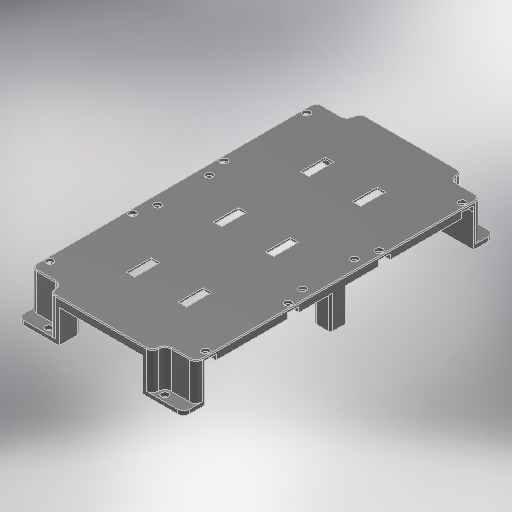
# Autodesk Inventor part: 3D_circuit-mount
Saved by Autodesk Inventor 2025.3 (Build 293356030, 356C)
## iProperties
Created: 2026-09-07
Part Number: 3D_circuit-mount
Material: 一般
Document SubType Name: Modeling
Designer: ibuki_ono
Density: 1 g/cm^3
Appearance: 滑らか - 黒
Author: ibuki_ono
## iProperties of the stored document 3D_circuit-mount_3D プリント.ipt
Created: 2026-09-07
Part Number: 3D_circuit-mount_3D プリント
Material: 一般
Document SubType Name: Modeling
Designer: ibuki_ono
Density: 1 g/cm^3
Appearance: 既定
Author: ibuki_ono
Autodesk Inventor part; units mm, degrees
ref_plane "YZ Plane" through (0, 0, 0) normal (1, 0, 0) x (0, 1, 0)
ref_plane "XZ Plane" through (0, 0, 0) normal (0, 1, 0) x (-1, 0, 0)
ref_plane "XY Plane" through (0, 0, 0) normal (0, 0, 1) x (1, 0, 0)
sketch "スケッチ1" plane through (0, 0, 0) normal (0, 1, 0) x (-1, 0, 0)
  line L0 (-28, 72) -> (28, 72) construction
  line L1 (28, 72) -> (28, -72) construction
  line L2 (28, -72) -> (-28, -72) construction
  line L3 (-28, -72) -> (-28, 72) construction
  line L4 (-28, 72) -> (28, -72) construction
  line L5 (28, 72) -> (-28, -72) construction
  line L6 (-40, -75) -> (40, -75)
  line L7 (40, -75) -> (40, 75)
  line L8 (40, 75) -> (-40, 75)
  line L9 (-40, 75) -> (-40, -75)
  line L10 (-40, -75) -> (40, 75) construction
  line L11 (40, -75) -> (-40, 75) construction
  point P0 (0, 0)
  dimension "d0" = 56
  dimension "d1" = 144
  dimension "d5" = 80
  dimension "d6" = 150
  constraints: 24 end point, 4 midpoint, 4 parallel, 2 horizontal, 2 perpendicular
  measures "d0" distance of L1.end L2.end
  measures "d1" distance of L0.end L1.end
  measures "d5" distance of L8.end L7.end
  measures "d6" distance of L7.end L6.end
extrude "押し出し1" add sketch "スケッチ1" along normal mid plane 2
sketch "スケッチ2" plane through (0, 1, 0) normal (0, 1, 0) x (1, 0, 0)
  line L0 (28, -72) -> (-28, -72) construction
  line L1 (-28, -72) -> (-28, 72) construction
  line L2 (-28, 72) -> (28, 72) construction
  line L3 (28, 72) -> (28, -72) construction
  line L4 (28, -72) -> (-28, 72) construction
  line L5 (-28, -72) -> (28, 72) construction
  line L6 (-40, 75) -> (-40, -75) projected
  line L7 (-40, -75) -> (40, -75) projected
  line L8 (40, -75) -> (40, 75) projected
  line L9 (40, 75) -> (-40, 75) projected
  circle A0 centre (-28, -72) radius 3
  circle A1 centre (28, -72) radius 3
  circle A2 centre (-28, 72) radius 3
  circle A3 centre (28, 72) radius 3
  line L10 (-40, -75) -> (40, -75) projected
  line L11 (40, 75) -> (-40, 75) projected
  line L12 (-28, -69) -> (-40, -69)
  line L13 (28, -69) -> (40, -69)
  line L14 (28, 69) -> (40, 69)
  line L15 (-28, 69) -> (-40, 69)
  line L16 (-25, -72) -> (-25, -75)
  line L17 (25, -72) -> (25, -75)
  line L18 (25, 72) -> (25, 75)
  line L19 (-25, 72) -> (-25, 75)
  point P0 (0, 0)
  dimension "d7" = 56
  dimension "d8" = 144
  constraints: 28 end point, 20 point on line, 8 point on circle, 7 tangent, 5 perpendicular, 4 centre point, 4 coincident, 2 midpoint, 2 parallel, 1 horizontal
  measures "d7" distance of L1.end L2.end
  measures "d8" distance of L0.end L1.end
extrude "押し出し2" add sketch "スケッチ2" along normal blind 18 contours L15 A2 L19 L9 L18 A3 L14 L8 L13 A1 L17 L7 L16 A0 L12 L6
sketch "スケッチ3" plane through (0, -1, 0) normal (0, -1, 0) x (1, 0, 0)
  arc A0 (-25, -72) -> (-28, -69) centre (-28, -72) ccw projected
  line L0 (-28, -69) -> (-40, -69) projected
  line L1 (-40, -69) -> (-40, 69) projected
  line L2 (-40, 69) -> (-28, 69) projected
  arc A1 (-28, 69) -> (-25, 72) centre (-28, 72) ccw projected
  line L3 (-25, 72) -> (-25, 75) projected
  line L4 (-25, 75) -> (25, 75) projected
  line L5 (25, 75) -> (25, 72) projected
  arc A2 (25, 72) -> (28, 69) centre (28, 72) ccw projected
  line L6 (28, 69) -> (40, 69) projected
  line L7 (40, 69) -> (40, -69) projected
  line L8 (40, -69) -> (28, -69) projected
  arc A3 (28, -69) -> (25, -72) centre (28, -72) ccw projected
  line L9 (25, -72) -> (25, -75) projected
  line L10 (25, -75) -> (-25, -75) projected
  line L11 (-25, -75) -> (-25, -72) projected
  line L12 (40, 65) -> (-40, 65)
  line L13 (40, -65) -> (-40, -65)
  line L14 (-40, 75) -> (-40, -75) projected
  line L15 (40, 75) -> (-40, 75) projected
  line L16 (-20, 75) -> (20, 75)
  line L17 (20, 75) -> (20, 65)
  line L18 (20, 65) -> (-20, 65)
  line L19 (-20, 65) -> (-20, 75)
  line L20 (-20, -65) -> (20, -65)
  line L21 (20, -65) -> (20, -75)
  line L22 (20, -75) -> (-20, -75)
  line L23 (-20, -75) -> (-20, -65)
  point P0 (0, 0)
  point P1 (0, 75)
  point P2 (0, -75)
  point P3 (-40, -65)
  dimension "d11" = 4
  dimension "d12" = 4
  dimension "d13" = 5
  dimension "d14" = 5
  constraints: 20 end point, 8 point on line, 4 midpoint, 4 parallel, 4 perpendicular, 2 horizontal
  measures "d11" distance between parallel lines of L6 L12
  measures "d12" distance between parallel lines of L8 L13
  measures "d13" distance between parallel lines of L17 L5
  measures "d14" distance between parallel lines of L9 L21
extrude "押し出し3" cut sketch "スケッチ3" against normal blind 16 contours L23 L13 L21 L10 | L1 L12 L7 L13 | L19 L4 L17 L12
sketch "スケッチ4" plane through (0, 15, 0) normal (0, -1, 0) x (1, 0, 0)
  line L0 (40, 65) -> (40, -65) projected
  line L1 (-40, -65) -> (-40, 65) projected
  line L2 (40, 4) -> (32, 4)
  line L3 (32, 4) -> (32, -4)
  line L4 (32, -4) -> (40, -4)
  line L5 (40, -4) -> (40, 4)
  line L6 (-40, 4) -> (-32, 4)
  line L7 (-32, 4) -> (-32, -4)
  line L8 (-32, -4) -> (-40, -4)
  line L9 (-40, -4) -> (-40, 4)
  point P0 (0, 0)
  point P1 (40, 0)
  point P2 (-40, 0)
  dimension "d17" = 8
  dimension "d18" = 8
  dimension "d19" = 8
  dimension "d20" = 8
  constraints: 16 end point, 4 midpoint, 4 parallel, 2 horizontal, 2 perpendicular, 2 point on line
  measures "d17" distance of L4.end L3.end
  measures "d18" distance of L3.end L2.end
  measures "d19" distance of L7.end L8.end
  measures "d20" distance of L6.end L7.end
extrude "押し出し4" add sketch "スケッチ4" along normal up to surface (16 mm away)
sketch "スケッチ5" plane through (0, 15, 0) normal (0, -1, 0) x (1, 0, 0)
  line L0 (-37.5, 62) -> (37.5, 62) construction
  line L1 (37.5, 62) -> (37.5, 22) construction
  line L2 (37.5, 22) -> (-37.5, 22) construction
  line L3 (-37.5, 22) -> (-37.5, 62) construction
  line L4 (-37.5, 62) -> (37.5, 22) construction
  line L5 (37.5, 62) -> (-37.5, 22) construction
  point P0 (0, 0)
  point P1 (0, 42)
  dimension "d23" = 75
  dimension "d24" = 40
  dimension "d25" = 42
  constraints: 12 end point, 4 coincident, 2 midpoint, 2 parallel, 1 horizontal, 1 perpendicular, 1 vertical alignment
  measures "d23" distance of L1.end L2.end
  measures "d24" distance of L0.end L1.end
  measures "d25" distance of point (0, 0) point (0, 42)
hole "穴1" at (37.5, 15, 62) at (37.5, 15, 22) at (-37.5, 15, 22) at (-37.5, 15, 62) direction (0, 1, 0) diameter 3.5 end through all
sketch "スケッチ6" plane through (0, 15, 0) normal (0, -1, 0) x (1, 0, 0)
  circle A0 centre (37.5, 62) radius 1.75 projected
  line L0 (35.9123, 59.25) -> (34.3246, 62)
  line L1 (34.3246, 62) -> (35.9123, 64.75)
  line L2 (35.9123, 64.75) -> (39.0877, 64.75)
  line L3 (39.0877, 64.75) -> (40.6754, 62)
  line L4 (40.6754, 62) -> (39.0877, 59.25)
  line L5 (39.0877, 59.25) -> (35.9123, 59.25)
  line L6 (40, 65) -> (40, 4) projected
  line L7 (39.0877, 64.75) -> (40, 64.75)
  line L8 (39.0877, 59.25) -> (40, 59.25)
  point P0 (0, 0)
  point P1 (40, 60.8301)
  point P2 (40, 63.1699)
  dimension "d33" = 5.5
  constraints: 16 end point, 2 perpendicular, 2 point on line, 1 coincident, 1 horizontal alignment, 13 other
  measures "d33" distance between parallel lines of L1 L4
extrude "押し出し5" cut sketch "スケッチ6" against normal blind 2.6
pattern_linear "矩形状パターン1" count 2 spacing 40 along (0, 0, -1) of "押し出し5"
mirror "ミラー1" about plane through (0, 0, 0) normal (1, 0, 0) of "押し出し5", "矩形状パターン1"
mirror "ミラー2" about plane through (0, 0, 0) normal (0, 0, 1) of "穴1", "押し出し5", "矩形状パターン1", "ミラー1"
sketch "スケッチ7" plane through (0, 15, 0) normal (0, -1, 0) x (1, 0, 0)
  line L0 (-25, -60) -> (25, -60)
  line L1 (25, -60) -> (25, 60)
  line L2 (25, 60) -> (-25, 60)
  line L3 (-25, 60) -> (-25, -60)
  line L4 (-25, -60) -> (25, 60) construction
  line L5 (25, -60) -> (-25, 60) construction
  point P0 (0, 0)
  dimension "d39" = 50
  dimension "d40" = 120
  constraints: 12 end point, 2 midpoint, 2 parallel, 1 horizontal, 1 perpendicular
  measures "d39" distance of L2.end L1.end
  measures "d40" distance of L1.end L0.end
extrude "押し出し6" cut sketch "スケッチ7" against normal blind 3
sketch "スケッチ8" plane through (0, 1, 0) normal (0, 1, 0) x (1, 0, 0)
  arc A0 (-25, -72) -> (-28, -69) centre (-28, -72) ccw projected
  arc A1 (28, -69) -> (25, -72) centre (28, -72) ccw projected
  arc A2 (25, 72) -> (28, 69) centre (28, 72) ccw projected
  arc A3 (-28, 69) -> (-25, 72) centre (-28, 72) ccw projected
  point P0 (0, 0)
  constraints: 4 coincident
hole "穴2" at (-28, 1, 72) at (28, 1, 72) at (28, 1, -72) at (-28, 1, -72) direction (0, -1, 0) diameter 3.5 end through all
fillet "フィレット1" radius 3 12 edges at (40, 0, 75) (40, 0, -75) (-40, 0, 75) (-40, 0, -75) (-25, 10, -75) (-40, 10, -69) (25, 10, -75) (40, 10, -69) (40, 10, 69) (25, 10, 75) (-25, 10, 75) (-40, 10, 69)
fillet "フィレット2" radius 1 12 edges at (40, 7, 4) (40, 7, -4) (32, 7, 4) (32, 7, -4) (-40, 7, 4) (-40, 7, -4) (-32, 7, 4) (-32, 7, -4) (20, 7, -65) (-20, 7, -65) (20, 7, 65) (-20, 7, 65)
fillet "フィレット3" radius 2 4 edges at (25, 16.5, 60) (-25, 16.5, 60) (-25, 16.5, -60) (25, 16.5, -60)
sketch "スケッチ9" plane through (0, 19, 0) normal (0, 1, 0) x (1, 0, 0)
  line L0 (-10.5, -6) -> (-14.5, -6)
  line L1 (-14.5, -6) -> (-14.5, 6)
  line L2 (-14.5, 6) -> (-10.5, 6)
  line L3 (-10.5, 6) -> (-10.5, -6)
  line L4 (-10.5, -6) -> (-14.5, 6) construction
  line L5 (-14.5, -6) -> (-10.5, 6) construction
  point P0 (0, 0)
  point P1 (-12.5, 0)
  dimension "d53" = 4
  dimension "d54" = 12
  dimension "d55" = 12.5
  constraints: 12 end point, 2 midpoint, 2 parallel, 1 horizontal, 1 horizontal alignment, 1 perpendicular
  measures "d53" distance of L1.end L2.end
  measures "d54" distance of L0.end L1.end
  measures "d55" distance of point (0, 0) point (-12.5, 0)
extrude "押し出し7" cut sketch "スケッチ9" against normal through all
mirror "ミラー3" about plane through (0, 0, 0) normal (1, 0, 0) of "押し出し7"
pattern_linear "矩形状パターン2" count 3 spacing 42 along (0, 0, -1) of "押し出し7", "ミラー3" first direction both ways yes
chamfer "面取り1" distance 0.4 angle 45 24 edges at (24.1213, 19, 74.1213) (25, 19, 72.0001) (0, 19, 75) (-24.1213, 19, 74.1213) (-25, 19, 72.0001) (-25.8787, 19, 69.8787) (-32.5, 19, 69) (-39.1213, 19, 68.1213) (-40, 19, 0) (-39.1213, 19, -68.1213) (-32.5001, 19, -69) (-25, 19, -72.0001) (-25.8787, 19, -69.8787) (-24.1213, 19, -74.1213) (0, 19, -75) (24.1213, 19, -74.1213) (25, 19, -72) (25.8787, 19, -69.8787) (32.5, 19, -69) (39.1213, 19, -68.1213) (40, 19, 0) (39.1213, 19, 68.1213) (32.5001, 19, 69) (25.8787, 19, 69.8787)
sketch "スケッチ10" plane through (0, 15, 0) normal (0, -1, 0) x (1, 0, 0)
  line L0 (-35, 12.5) -> (35, 12.5) construction
  line L1 (35, 12.5) -> (35, -12.5) construction
  line L2 (35, -12.5) -> (-35, -12.5) construction
  line L3 (-35, -12.5) -> (-35, 12.5) construction
  line L4 (-35, 12.5) -> (35, -12.5) construction
  line L5 (35, 12.5) -> (-35, -12.5) construction
  point P0 (0, 0)
  dimension "d64" = 70
  dimension "d65" = 25
  constraints: 12 end point, 4 coincident, 2 midpoint, 2 parallel, 1 horizontal, 1 perpendicular
  measures "d64" distance of L1.end L2.end
  measures "d65" distance of L0.end L1.end
hole "穴3" at (35, 15, 12.5) at (35, 15, -12.5) at (-35, 15, -12.5) at (-35, 15, 12.5) direction (0, 1, 0) diameter 3.5 end through all
sketch "スケッチ11" plane through (0, 15, 0) normal (0, -1, 0) x (1, 0, 0)
  circle A0 centre (35, 12.5) radius 1.75 projected
  line L0 (31.8246, 12.5) -> (33.4123, 15.25)
  line L1 (33.4123, 15.25) -> (36.5877, 15.25)
  line L2 (36.5877, 15.25) -> (38.1754, 12.5)
  line L3 (38.1754, 12.5) -> (36.5877, 9.75)
  line L4 (36.5877, 9.75) -> (33.4123, 9.75)
  line L5 (33.4123, 9.75) -> (31.8246, 12.5)
  point P0 (0, 0)
  dimension "d73" = 5.5
  constraints: 12 end point, 1 coincident, 1 horizontal alignment, 13 other
  measures "d73" distance between parallel lines of L4 L1
extrude "押し出し8" cut sketch "スケッチ11" against normal blind 2.6 contours A0 | L0 L1 L2 L3 L4 L5
pattern_linear "矩形状パターン3" count 2 spacing 25 along (0, 0, -1) count 2 spacing 70 along (-1, 0, 0) of "押し出し8"
equation "\"d12\" = d11"
equation "\"d14\" = d13"
